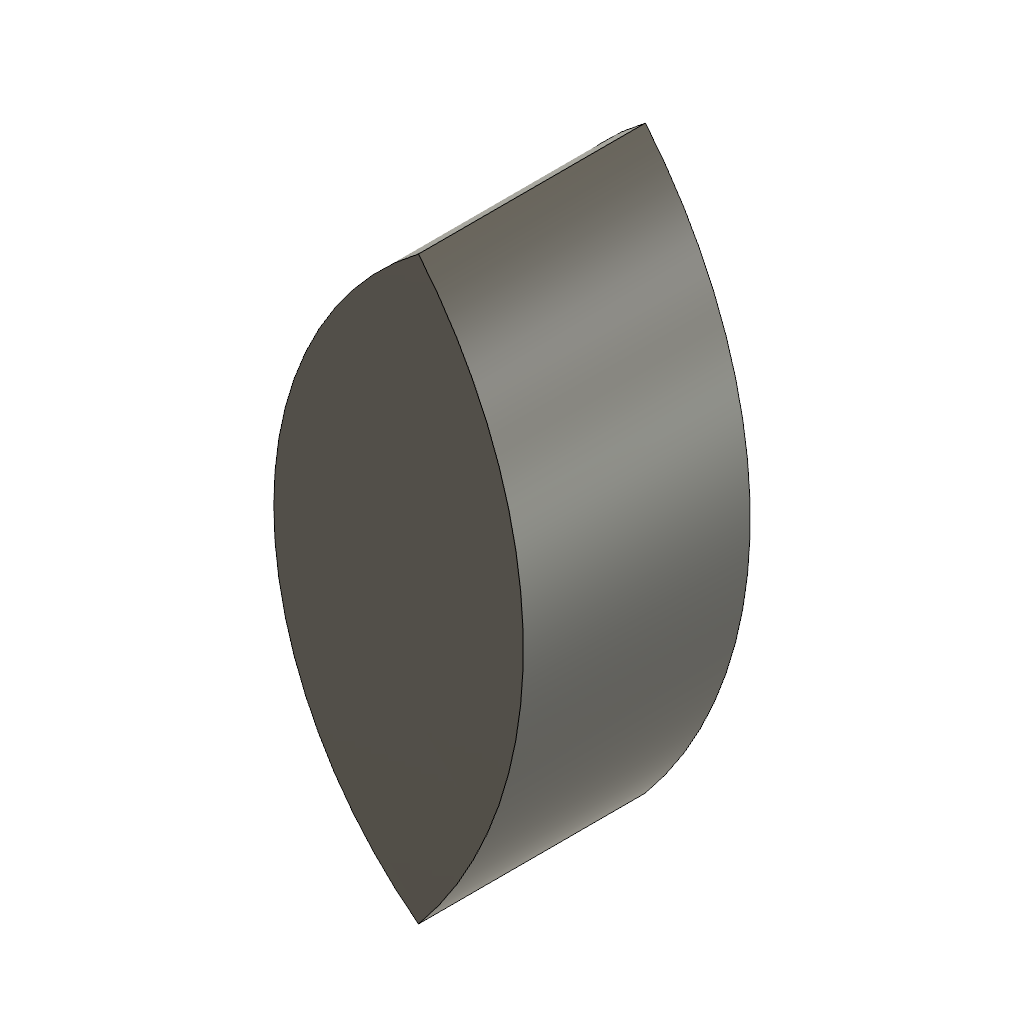
shifted_unequal_lens (Autodesk Fusion 360 design; units mm, degrees)
part number: 2026-10-21-11-33-12-925
Autodesk Fusion 360 part; units mm, degrees
sketch "TrimmedProfileSources" plane through (0, 0, 0) normal (0, 0, 1) x (1, 0, 0)
  circle A0 centre (-10, 0) radius 20
  circle A1 centre (15, 0) radius 16
extrude "SelectedTrimmedProfile" add sketch "TrimmedProfileSources" along normal blind 10 contours A0 A1 picked at (6.2828, 1.3012)
